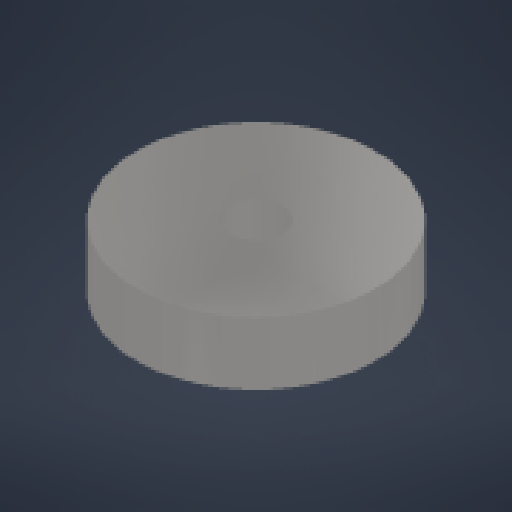
# Autodesk Inventor part: Pulley-Allen
Saved by Autodesk Inventor 2027.1 (Build 311270010, 270A)
## iProperties
Created: 2025-09-16
Part Number: Pulley-Allen
Material: Steel, Cast
Document SubType Name: Modeling
Designer: SD
Density: 7.85 g/cm^3
Appearance: Semi-Polished
Project: Automatic Tea Steeping mechanism
BOM-Mass: 0.06434
BOM-Area: 0.005
Diameter: 40.000 mm
Procurement: Fabricate - 1st round
Build Stage: 1
Preferred Material: Manufacturer Specification
Author: SD
Title: Pully
Autodesk Inventor part; units mm, degrees
ref_plane "YZ Plane" through (0, 0, 0) normal (1, 0, 0) x (0, 1, 0)
ref_plane "XZ Plane" through (0, 0, 0) normal (0, 1, 0) x (-1, 0, 0)
ref_plane "XY Plane" through (0, 0, 0) normal (0, 0, 1) x (1, 0, 0)
sketch "Sketch3" plane through (0, 0, 0) normal (0, 1, 0) x (-1, 0, 0)
  circle A0 centre (0, 0) radius 4.1
  circle A1 centre (0, 0) radius 19.05
  dimension "d21" = 8.2
  dimension "d22" = 38.1
  constraints: 2 centre point, 2 coincident
  measures "d21" diameter of A0
  measures "d22" diameter of A1
extrude "Extrusion1" add sketch "Sketch3" along normal mid plane 10
equation "\"Diameter\" = 40"
body "Solid2"
